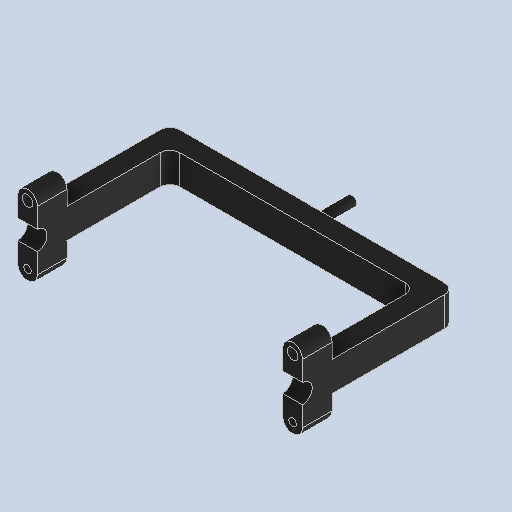
# Autodesk Inventor part: Stabilisatuer2.1
Saved by Autodesk Inventor 2025.3 (Build 293356000, 356)
## iProperties
Created: 2025-04-25
Part Number: Stabilisatuer2.1
Material: Gummi
Document SubType Name: Modeling
Designer: karle
Density: 0.93 g/cm^3
Appearance: Gummi - Schwarz
Author: karle
Autodesk Inventor part; units mm, degrees
ref_plane "YZ Plane" through (0, 0, 0) normal (1, 0, 0) x (0, 1, 0)
ref_plane "XZ Plane" through (0, 0, 0) normal (0, 1, 0) x (-1, 0, 0)
ref_plane "XY Plane" through (0, 0, 0) normal (0, 0, 1) x (1, 0, 0)
sketch "Skizze1" plane through (0, 0, 0) normal (0, 0, 1) x (1, 0, 0)
  line L0 (-72, 0) -> (-62, 0)
  line L1 (-62, 0) -> (-62, 67)
  line L2 (-62, 67) -> (62, 67)
  line L3 (62, 67) -> (62, 0)
  line L4 (62, 0) -> (72, 0)
  line L5 (72, 0) -> (72, 77)
  line L6 (72, 77) -> (-72, 77)
  line L7 (-72, 77) -> (-72, 0)
  line L8 (0, 90.2324) -> (0, 0)
  point P0 (67, 0)
  point P1 (0, 77)
  point P2 (0, 67)
  dimension "d0" = 124
  dimension "d1" = 67
  dimension "d2" = 0
  dimension "d3" = 62
  dimension "d4" = 144
  dimension "d5" = 10
  constraints: 18 end point, 6 perpendicular, 2 point on line, 1 horizontal, 1 midpoint, 1 vertical, 1 other
  measures "d0" distance between parallel lines of L1 L3
  measures "d1" distance from line of point (67, 0) L2
  measures "d2" vertical distance of L8.end point (67, 0)
  measures "d3" distance from line of L3 L8.end
  measures "d4" distance between parallel lines of L5 L7
  measures "d5" distance between parallel lines of L6 L2
extrude "Extrusion1" add sketch "Skizze1" along normal mid plane 15
sketch "Skizze2" plane through (-72, 0, 7.5) normal (0, -1, 0) x (1, 0, 0)
  line L0 (0, 12.5) -> (10, 12.5)
  line L1 (10, 12.5) -> (10, -27.5)
  line L2 (10, -27.5) -> (0, -27.5)
  line L3 (0, -27.5) -> (0, 12.5)
  line L4 (134, 12.5) -> (144, 12.5)
  line L5 (144, 12.5) -> (144, -27.5)
  line L6 (144, -27.5) -> (134, -27.5)
  line L7 (134, -27.5) -> (134, 12.5)
  line L8 (144, -15) -> (144, 0) projected
  line L9 (134, -15) -> (134, 0) projected
  line L10 (0, -15) -> (0, 0) projected
  line L11 (10, -15) -> (10, 0) projected
  line L12 (171.2366, -7.5) -> (-10.2497, -7.5)
  point P0 (72, -7.5)
  point P1 (139, -27.5)
  point P2 (139, 12.5)
  point P3 (139, -22.5)
  point P4 (5, -20.9733)
  point P5 (5, 5.9733)
  point P6 (139, 7.5)
  dimension "d8" = 40
  dimension "d9" = 12.5
  dimension "d12" = 30
  dimension "d14" = 5
  dimension "d16" = 5
  constraints: 18 end point, 4 collinear, 4 parallel, 3 horizontal, 2 midpoint, 2 perpendicular, 2 point on line, 2 symmetric about line, 1 other
  measures "d8" distance of point (139, -27.5) point (139, 12.5)
  measures "d9" distance from line of L8.end L0
  measures "d12" distance of point (139, 7.5) point (139, -22.5)
  measures "d14" distance from line of L7 point (139, -22.5)
  measures "d16" distance from line of L1 point (5, -20.973)
extrude "Extrusion2" add sketch "Skizze2" against normal blind 15
sketch "Skizze8" plane through (-72, 0, 20) normal (0, -1, 0) x (1, 0, 0)
  line L0 (0, -40) -> (0, 0) projected
  line L1 (10, 0) -> (0, 0) projected
  point P0 (72, -20)
  point P1 (5, -5)
  point P2 (5, -35)
  point P3 (139, -35)
  point P4 (139, -5)
  dimension "d55" = 5
  dimension "d56" = 30
  dimension "d57" = 134
  dimension "d58" = 5
  constraints: 2 horizontal alignment, 2 vertical alignment
  measures "d55" distance from line of L0 point (5, -5)
  measures "d56" distance of point (5, -5) point (5, -35)
  measures "d57" distance of point (139, -35) point (5, -35)
  measures "d58" distance from line of L1 point (5, -5)
hole "Bohrung5" at (-67, 0, 15) at (67, 0, 15) direction (0, 1, 0) diameter 5.5 depth 13
hole "Bohrung6" at (-67, 0, -15) at (67, 0, -15) direction (0, 1, 0) diameter 3.8 end through all
fillet "Rundung2" radius 5 8 edges at (62, 7.5, -20) (62, 7.5, 20) (72, 7.5, -20) (72, 7.5, 20) (-62, 7.5, 20) (-72, 7.5, 20) (-72, 7.5, -20) (-62, 7.5, -20)
fillet "Rundung3" radius 5 4 edges at (-62, 67, 0) (-72, 77, 0) (72, 77, 0) (62, 67, 0)
sketch "Skizze9" plane through (72, 0, 15.0251) normal (1, 0, 0) x (0, 0, -1)
  point P0 (15.0251, 0)
  point P1 (15.0251, 0)
  constraints: 1 coincident
hole "Bohrung7" at (72, 0, 0) direction (-1, 0, 0) diameter 9.8 end through all
sketch "Skizze10" plane through (-67, 77, -7.5) normal (0, 1, 0) x (1, 0, 0)
  circle A0 centre (67, -7.5) radius 2.4
  dimension "d82" = 4.8
  constraints: 1 centre point, 1 coincident
  measures "d82" diameter of A0
extrude "Extrusion3" add sketch "Skizze10" along normal blind 20
fillet "Rundung4" radius 5 1 edges at (-2.4, 77, 0)
